Autodesk Fusion 360 part; units mm, degrees
(part 2 of 2)
sketch "Slot 2 50 constrained seed (3)" plane through (0, 0, 0) normal (0, 0, 1) x (1, 0, 0) in component "Solid-land M3"
  line L0 (167.5, 45) -> (167.5, 55)
  arc A0 (167.5, 55) -> (162.5, 55) centre (165, 55) ccw
  line L1 (162.5, 55) -> (162.5, 45)
  arc A1 (162.5, 45) -> (167.5, 45) centre (165, 45) ccw
  line L2 (165, 45) -> (165, 55) construction
  line L3 (165, 45) -> (175, 45) construction
  dimension "d538" = 5
  dimension "d539" = 10
  dimension "d540" = 90
  dimension "d541" = 10
  dimension "d542" = 165
  dimension "d543" = 45
  constraint tangent L0 A0
  constraint tangent A0 L1
  constraint tangent L1 A1
  constraint tangent L0 A1
  constraint parallel L0 L1
  constraint horizontal L3
  measures "d538" diameter of A0
  measures "d539" distance of A1.centre A0.centre
  measures "d540" angle of L2 L3
  measures "d541" horizontal distance of A1.centre L3.end
  measures "d542" horizontal distance of origin A1.centre
  measures "d543" vertical distance of origin A1.centre
extrude "Slot 2 50 through cut''" cut sketch "Slot 2 50 constrained seed (3)" along normal blind 5 bodies 3 in component "Solid-land M3"
pattern_linear "Slot 2 50 lattice''" count 1 spacing 20 along (1, 0, 0) of "Slot 2 50 through cut''" in component "Solid-land M3"
sketch "Slot 3 20 constrained seed (3)" plane through (0, 0, 0) normal (0, 0, 1) x (1, 0, 0) in component "Solid-land M3"
  line L0 (177.5, 15) -> (177.5, 25)
  arc A0 (177.5, 25) -> (172.5, 25) centre (175, 25) ccw
  line L1 (172.5, 25) -> (172.5, 15)
  arc A1 (172.5, 15) -> (177.5, 15) centre (175, 15) ccw
  line L2 (175, 15) -> (175, 25) construction
  line L3 (175, 15) -> (185, 15) construction
  dimension "d550" = 5
  dimension "d551" = 10
  dimension "d552" = 90
  dimension "d553" = 10
  dimension "d554" = 175
  dimension "d555" = 15
  constraint tangent L0 A0
  constraint tangent A0 L1
  constraint tangent L1 A1
  constraint tangent L0 A1
  constraint parallel L0 L1
  constraint horizontal L3
  measures "d550" diameter of A0
  measures "d551" distance of A1.centre A0.centre
  measures "d552" angle of L2 L3
  measures "d553" horizontal distance of A1.centre L3.end
  measures "d554" horizontal distance of origin A1.centre
  measures "d555" vertical distance of origin A1.centre
extrude "Slot 3 20 through cut''" cut sketch "Slot 3 20 constrained seed (3)" along normal blind 5 bodies 3 in component "Solid-land M3"
pattern_linear "Slot 3 20 lattice''" count 1 spacing 20 along (1, 0, 0) of "Slot 3 20 through cut''" in component "Solid-land M3"
sketch "Slot 3 40 constrained seed (3)" plane through (0, 0, 0) normal (0, 0, 1) x (1, 0, 0) in component "Solid-land M3"
  line L0 (177.5, 35) -> (177.5, 45)
  arc A0 (177.5, 45) -> (172.5, 45) centre (175, 45) ccw
  line L1 (172.5, 45) -> (172.5, 35)
  arc A1 (172.5, 35) -> (177.5, 35) centre (175, 35) ccw
  line L2 (175, 35) -> (175, 45) construction
  line L3 (175, 35) -> (185, 35) construction
  dimension "d562" = 5
  dimension "d563" = 10
  dimension "d564" = 90
  dimension "d565" = 10
  dimension "d566" = 175
  dimension "d567" = 35
  constraint tangent L0 A0
  constraint tangent A0 L1
  constraint tangent L1 A1
  constraint tangent L0 A1
  constraint parallel L0 L1
  constraint horizontal L3
  measures "d562" diameter of A0
  measures "d563" distance of A1.centre A0.centre
  measures "d564" angle of L2 L3
  measures "d565" horizontal distance of A1.centre L3.end
  measures "d566" horizontal distance of origin A1.centre
  measures "d567" vertical distance of origin A1.centre
extrude "Slot 3 40 through cut''" cut sketch "Slot 3 40 constrained seed (3)" along normal blind 5 bodies 3 in component "Solid-land M3"
pattern_linear "Slot 3 40 lattice''" count 1 spacing 20 along (1, 0, 0) of "Slot 3 40 through cut''" in component "Solid-land M3"
sketch "Slot 4 10 constrained seed (3)" plane through (0, 0, 0) normal (0, 0, 1) x (1, 0, 0) in component "Solid-land M3"
  line L0 (187.5, 5) -> (187.5, 15)
  arc A0 (187.5, 15) -> (182.5, 15) centre (185, 15) ccw
  line L1 (182.5, 15) -> (182.5, 5)
  arc A1 (182.5, 5) -> (187.5, 5) centre (185, 5) ccw
  line L2 (185, 5) -> (185, 15) construction
  line L3 (185, 5) -> (195, 5) construction
  dimension "d574" = 5
  dimension "d575" = 10
  dimension "d576" = 90
  dimension "d577" = 10
  dimension "d578" = 185
  dimension "d579" = 5
  constraint tangent L0 A0
  constraint tangent A0 L1
  constraint tangent L1 A1
  constraint tangent L0 A1
  constraint parallel L0 L1
  constraint horizontal L3
  measures "d574" diameter of A0
  measures "d575" distance of A1.centre A0.centre
  measures "d576" angle of L2 L3
  measures "d577" horizontal distance of A1.centre L3.end
  measures "d578" horizontal distance of origin A1.centre
  measures "d579" vertical distance of origin A1.centre
extrude "Slot 4 10 through cut''" cut sketch "Slot 4 10 constrained seed (3)" along normal blind 5 bodies 3 in component "Solid-land M3"
pattern_linear "Slot 4 10 lattice''" count 1 spacing 20 along (1, 0, 0) of "Slot 4 10 through cut''" in component "Solid-land M3"
sketch "Slot 4 30 constrained seed (3)" plane through (0, 0, 0) normal (0, 0, 1) x (1, 0, 0) in component "Solid-land M3"
  line L0 (187.5, 25) -> (187.5, 35)
  arc A0 (187.5, 35) -> (182.5, 35) centre (185, 35) ccw
  line L1 (182.5, 35) -> (182.5, 25)
  arc A1 (182.5, 25) -> (187.5, 25) centre (185, 25) ccw
  line L2 (185, 25) -> (185, 35) construction
  line L3 (185, 25) -> (195, 25) construction
  dimension "d586" = 5
  dimension "d587" = 10
  dimension "d588" = 90
  dimension "d589" = 10
  dimension "d590" = 185
  dimension "d591" = 25
  constraint tangent L0 A0
  constraint tangent A0 L1
  constraint tangent L1 A1
  constraint tangent L0 A1
  constraint parallel L0 L1
  constraint horizontal L3
  measures "d586" diameter of A0
  measures "d587" distance of A1.centre A0.centre
  measures "d588" angle of L2 L3
  measures "d589" horizontal distance of A1.centre L3.end
  measures "d590" horizontal distance of origin A1.centre
  measures "d591" vertical distance of origin A1.centre
extrude "Slot 4 30 through cut''" cut sketch "Slot 4 30 constrained seed (3)" along normal blind 5 bodies 3 in component "Solid-land M3"
pattern_linear "Slot 4 30 lattice''" count 1 spacing 20 along (1, 0, 0) of "Slot 4 30 through cut''" in component "Solid-land M3"
sketch "Slot 4 50 constrained seed (3)" plane through (0, 0, 0) normal (0, 0, 1) x (1, 0, 0) in component "Solid-land M3"
  line L0 (187.5, 45) -> (187.5, 55)
  arc A0 (187.5, 55) -> (182.5, 55) centre (185, 55) ccw
  line L1 (182.5, 55) -> (182.5, 45)
  arc A1 (182.5, 45) -> (187.5, 45) centre (185, 45) ccw
  line L2 (185, 45) -> (185, 55) construction
  line L3 (185, 45) -> (195, 45) construction
  dimension "d598" = 5
  dimension "d599" = 10
  dimension "d600" = 90
  dimension "d601" = 10
  dimension "d602" = 185
  dimension "d603" = 45
  constraint tangent L0 A0
  constraint tangent A0 L1
  constraint tangent L1 A1
  constraint tangent L0 A1
  constraint parallel L0 L1
  constraint horizontal L3
  measures "d598" diameter of A0
  measures "d599" distance of A1.centre A0.centre
  measures "d600" angle of L2 L3
  measures "d601" horizontal distance of A1.centre L3.end
  measures "d602" horizontal distance of origin A1.centre
  measures "d603" vertical distance of origin A1.centre
extrude "Slot 4 50 through cut''" cut sketch "Slot 4 50 constrained seed (3)" along normal blind 5 bodies 3 in component "Solid-land M3"
pattern_linear "Slot 4 50 lattice''" count 1 spacing 20 along (1, 0, 0) of "Slot 4 50 through cut''" in component "Solid-land M3"
sketch "Slot 5 20 constrained seed (3)" plane through (0, 0, 0) normal (0, 0, 1) x (1, 0, 0) in component "Solid-land M3"
  line L0 (197.5, 15) -> (197.5, 25)
  arc A0 (197.5, 25) -> (192.5, 25) centre (195, 25) ccw
  line L1 (192.5, 25) -> (192.5, 15)
  arc A1 (192.5, 15) -> (197.5, 15) centre (195, 15) ccw
  line L2 (195, 15) -> (195, 25) construction
  line L3 (195, 15) -> (205, 15) construction
  dimension "d610" = 5
  dimension "d611" = 10
  dimension "d612" = 90
  dimension "d613" = 10
  dimension "d614" = 195
  dimension "d615" = 15
  constraint tangent L0 A0
  constraint tangent A0 L1
  constraint tangent L1 A1
  constraint tangent L0 A1
  constraint parallel L0 L1
  constraint horizontal L3
  measures "d610" diameter of A0
  measures "d611" distance of A1.centre A0.centre
  measures "d612" angle of L2 L3
  measures "d613" horizontal distance of A1.centre L3.end
  measures "d614" horizontal distance of origin A1.centre
  measures "d615" vertical distance of origin A1.centre
extrude "Slot 5 20 through cut''" cut sketch "Slot 5 20 constrained seed (3)" along normal blind 5 bodies 3 in component "Solid-land M3"
pattern_linear "Slot 5 20 lattice''" count 1 spacing 20 along (1, 0, 0) of "Slot 5 20 through cut''" in component "Solid-land M3"
sketch "Slot 5 40 constrained seed (3)" plane through (0, 0, 0) normal (0, 0, 1) x (1, 0, 0) in component "Solid-land M3"
  line L0 (197.5, 35) -> (197.5, 45)
  arc A0 (197.5, 45) -> (192.5, 45) centre (195, 45) ccw
  line L1 (192.5, 45) -> (192.5, 35)
  arc A1 (192.5, 35) -> (197.5, 35) centre (195, 35) ccw
  line L2 (195, 35) -> (195, 45) construction
  line L3 (195, 35) -> (205, 35) construction
  dimension "d622" = 5
  dimension "d623" = 10
  dimension "d624" = 90
  dimension "d625" = 10
  dimension "d626" = 195
  dimension "d627" = 35
  constraint tangent L0 A0
  constraint tangent A0 L1
  constraint tangent L1 A1
  constraint tangent L0 A1
  constraint parallel L0 L1
  constraint horizontal L3
  measures "d622" diameter of A0
  measures "d623" distance of A1.centre A0.centre
  measures "d624" angle of L2 L3
  measures "d625" horizontal distance of A1.centre L3.end
  measures "d626" horizontal distance of origin A1.centre
  measures "d627" vertical distance of origin A1.centre
extrude "Slot 5 40 through cut''" cut sketch "Slot 5 40 constrained seed (3)" along normal blind 5 bodies 3 in component "Solid-land M3"
pattern_linear "Slot 5 40 lattice''" count 1 spacing 20 along (1, 0, 0) of "Slot 5 40 through cut''" in component "Solid-land M3"
fillet "Rounded entrances''" radius 0.4 2 faces at (194.1044, 5.8357, 0) (194.1044, 5.8357, 0) on bodies 3 in component "Solid-land M3"
sketch "Mount bore sketch (3)" plane through (0, 0, 0) normal (0, 0, 1) x (1, 0, 0) in component "Solid-land M3"
  circle A0 centre (165, 30) radius 1.7
  dimension "d636" = 165
  dimension "d637" = 30
  dimension "d638" = 3.4
  measures "d636" horizontal distance of origin A0.centre
  measures "d637" vertical distance of origin A0.centre
  measures "d638" diameter of A0
extrude "Mount bore''" cut sketch "Mount bore sketch (3)" along normal blind 5 bodies 3 in component "Solid-land M3"
sketch "Flush screw seat sketch (3)" plane through (0, 0, 0) normal (0, 0, 1) x (1, 0, 0) in component "Solid-land M3"
  circle A0 centre (165, 30) radius 3.1
  dimension "d641" = 165
  dimension "d642" = 30
  dimension "d643" = 6.2
  measures "d641" horizontal distance of origin A0.centre
  measures "d642" vertical distance of origin A0.centre
  measures "d643" diameter of A0
extrude "Flush screw seat''" cut sketch "Flush screw seat sketch (3)" along normal blind 1.4 draft -45 bodies 3 in component "Solid-land M3"
component "Original M2" placed x (1, 0, 0) y (0, 1, 0) z (0, 0, 1) at (0, 0, 0)
component "Centered M2" placed x (1, 0, 0) y (0, 1, 0) z (0, 0, 1) at (0, 0, 0)
component "Solid-land M3" placed x (1, 0, 0) y (0, 1, 0) z (0, 0, 1) at (0, 0, 0)
equation "columns = 12" comment "Even integer 4..14; each cell is 20 mm"
equation "rows = 12" comment "Even integer 4..14"
equation "pitch = 20 mm" comment "Keep for dense SKADIS compatible lattice"
equation "panelWidth = columns * pitch" comment "Nominal module pitch X"
equation "panelHeight = rows * pitch" comment "Nominal module pitch Y"
equation "seamGap = 0.35 mm" comment "Physical envelope shrinks around fixed lattice"
equation "boardThickness = 5 mm" comment "Fit-test with real hooks"
equation "slotWidth = 5 mm" comment "Minimum throat width"
equation "slotHeight = 15 mm" comment "Minimum throat height"
equation "entryRadius = 0.4 mm" comment "Front slot and perimeter edge rounding"
equation "cornerRadius = 6 mm" comment "Plan-view panel corner rounding"
equation "hookClearance = 10 mm" comment "PROVISIONAL unobstructed depth behind board; carriers begin at its rear boundary"
equation "frameZ = carrierZ + carrierThickness" comment "Front extrusion datum"
equation "profileMouth = 6.28 mm" comment "User measured mouth"
equation "profileCavity = 11 mm" comment "User measured widest cavity"
equation "profileDepth = 6.2 mm" comment "User measured face-to-floor depth"
equation "profileFloor = 5.7 mm" comment "User estimate, lower confidence"
equation "profileLip = 1.5 mm" comment "Unmeasured; tentative comparable catalog value"
equation "profileTaperStart = profileDepth - ( profileCavity - profileFloor ) / 2" comment "Assumed 45-degree inner slopes"
equation "profileBore = 5 mm" comment "Unmeasured central bore, reference only"
equation "nutWidth = 8.8 mm" comment "Provisional low-profile METAL T-nut envelope, not old rectangular carrier"
equation "nutLength = 12 mm" comment "End-loaded anti-rotation metal nut envelope"
equation "nutThickness = 2.7 mm" comment "Thin nut reference; fit/load still unverified"
equation "jointLeg = 18 mm" comment "In-bay angle footprint"
equation "jointThickness = 3 mm" comment "Metal bracket thickness"
equation "jointDepth = 16 mm" comment "Bracket depth within 20 mm rail"
equation "sideScrewLength = 8 mm" comment "M5x8 reference; check against actual bracket and nut"
equation "wallTabHeight = 24 mm" comment "Tab along extrusion"
equation "wallTabReach = 22 mm" comment "Tab into open bay"
equation "wallAnchorClearance = 6.5 mm" comment "Placeholder wall anchor interface"
equation "wallDriverDiameter = 12 mm" comment "Clear tool envelope in open bays"
equation "keyDriverDiameter = 5 mm" comment "Short hex-key working-leg envelope"
equation "keyDriverReach = 20 mm" comment "Short hex-key working-leg reach"
equation "supportWidth = 3.2 mm" comment "Prototype blade; two perimeter lines need print review"
equation "supportLength = 12 mm" comment "Compression bearing length"
equation "hookEnvelopeWidth = 6 mm" comment "Conservative provisional continuous hook column"
equation "carrierThickness = 7 mm" comment "Room for captive M2 nut and stock M5x12"
equation "panelClearance = 2.4 mm" comment "M2 clearance"
equation "panelHeadPocket = 4 mm" comment "DIN965 3.8 mm head plus 0.1 mm recess"
equation "carrierHeadPocket = 9.4 mm" comment "DIN965 M5 9.2 mm head plus recess"
equation "carrierBore = 5.5 mm" comment "M5 clearance"
equation "tongueWidth = 2.8 mm" comment "Rear axial registration tongue"
equation "tongueLength = 8 mm" comment "Axial release registration"
equation "tongueDepth = 0.6 mm" comment "Tongue engagement"
equation "registerClearance = 0.2 mm" comment "Each side of printed tongue"
equation "carrierZ = boardThickness + hookClearance" comment "Rear hook cavity boundary"
equation "stepCorner = 0.6 mm" comment "Small plan corner relief; printed fit remains untested"
equation "webCenterOffset = ( pitch / 2 - ( pitch - ( slotHeight - slotWidth ) ) / 2 ) ^ 2 / pitch" comment "Equal clearance to three adjacent slot outlines; 1.25 mm at standard lattice"
equation "d70 = boardThickness"
equation "d72 = slotWidth"
equation "d73 = slotHeight - slotWidth"
equation "d75 = pitch / 2"
equation "d76 = abs(5 mm)"
equation "d77 = abs(( 10 mm ) - ( slotHeight - slotWidth ) / 2)"
equation "d78 = boardThickness"
equation "d82 = pitch"
equation "d83 = pitch"
equation "d84 = slotWidth"
equation "d85 = slotHeight - slotWidth"
equation "d87 = pitch / 2"
equation "d88 = abs(5 mm)"
equation "d89 = abs(( 30 mm ) - ( slotHeight - slotWidth ) / 2)"
equation "d90 = boardThickness"
equation "d94 = pitch"
equation "d95 = pitch"
equation "d96 = slotWidth"
equation "d97 = slotHeight - slotWidth"
equation "d99 = pitch / 2"
equation "d100 = abs(5 mm)"
equation "d101 = abs(( 50 mm ) - ( slotHeight - slotWidth ) / 2)"
equation "d102 = boardThickness"
equation "d106 = pitch"
equation "d107 = pitch"
equation "d108 = slotWidth"
equation "d109 = slotHeight - slotWidth"
equation "d111 = pitch / 2"
equation "d112 = abs(15 mm)"
equation "d113 = abs(( 20 mm ) - ( slotHeight - slotWidth ) / 2)"
equation "d114 = boardThickness"
equation "d118 = pitch"
equation "d119 = pitch"
equation "d120 = slotWidth"
equation "d121 = slotHeight - slotWidth"
equation "d123 = pitch / 2"
equation "d124 = abs(15 mm)"
equation "d125 = abs(( 40 mm ) - ( slotHeight - slotWidth ) / 2)"
equation "d126 = boardThickness"
equation "d130 = pitch"
equation "d131 = pitch"
equation "d132 = slotWidth"
equation "d133 = slotHeight - slotWidth"
equation "d135 = pitch / 2"
equation "d136 = abs(25 mm)"
equation "d137 = abs(( 10 mm ) - ( slotHeight - slotWidth ) / 2)"
equation "d138 = boardThickness"
equation "d142 = pitch"
equation "d143 = pitch"
equation "d144 = slotWidth"
equation "d145 = slotHeight - slotWidth"
equation "d147 = pitch / 2"
equation "d148 = abs(25 mm)"
equation "d149 = abs(( 30 mm ) - ( slotHeight - slotWidth ) / 2)"
equation "d150 = boardThickness"
equation "d154 = pitch"
equation "d155 = pitch"
equation "d156 = slotWidth"
equation "d157 = slotHeight - slotWidth"
equation "d159 = pitch / 2"
equation "d160 = abs(25 mm)"
equation "d161 = abs(( 50 mm ) - ( slotHeight - slotWidth ) / 2)"
equation "d162 = boardThickness"
equation "d166 = pitch"
equation "d167 = pitch"
equation "d168 = slotWidth"
equation "d169 = slotHeight - slotWidth"
equation "d171 = pitch / 2"
equation "d172 = abs(35 mm)"
equation "d173 = abs(( 20 mm ) - ( slotHeight - slotWidth ) / 2)"
equation "d174 = boardThickness"
equation "d178 = pitch"
equation "d179 = pitch"
equation "d180 = slotWidth"
equation "d181 = slotHeight - slotWidth"
equation "d183 = pitch / 2"
equation "d184 = abs(35 mm)"
equation "d185 = abs(( 40 mm ) - ( slotHeight - slotWidth ) / 2)"
equation "d186 = boardThickness"
equation "d190 = pitch"
equation "d191 = pitch"
equation "d192 = slotWidth"
equation "d193 = slotHeight - slotWidth"
equation "d195 = pitch / 2"
equation "d196 = abs(45 mm)"
equation "d197 = abs(( 10 mm ) - ( slotHeight - slotWidth ) / 2)"
equation "d198 = boardThickness"
equation "d202 = pitch"
equation "d203 = pitch"
equation "d204 = slotWidth"
equation "d205 = slotHeight - slotWidth"
equation "d207 = pitch / 2"
equation "d208 = abs(45 mm)"
equation "d209 = abs(( 30 mm ) - ( slotHeight - slotWidth ) / 2)"
equation "d210 = boardThickness"
equation "d214 = pitch"
equation "d215 = pitch"
equation "d216 = slotWidth"
equation "d217 = slotHeight - slotWidth"
equation "d219 = pitch / 2"
equation "d220 = abs(45 mm)"
equation "d221 = abs(( 50 mm ) - ( slotHeight - slotWidth ) / 2)"
equation "d222 = boardThickness"
equation "d226 = pitch"
equation "d227 = pitch"
equation "d228 = slotWidth"
equation "d229 = slotHeight - slotWidth"
equation "d231 = pitch / 2"
equation "d232 = abs(55 mm)"
equation "d233 = abs(( 20 mm ) - ( slotHeight - slotWidth ) / 2)"
equation "d234 = boardThickness"
equation "d238 = pitch"
equation "d239 = pitch"
equation "d240 = slotWidth"
equation "d241 = slotHeight - slotWidth"
equation "d243 = pitch / 2"
equation "d244 = abs(55 mm)"
equation "d245 = abs(( 40 mm ) - ( slotHeight - slotWidth ) / 2)"
equation "d246 = boardThickness"
equation "d250 = pitch"
equation "d251 = pitch"
equation "d253 = entryRadius"
equation "d254 = abs(30 mm)"
equation "d255 = abs(20 mm)"
equation "d257 = boardThickness"
equation "d259 = abs(30 mm)"
equation "d260 = abs(20 mm)"
equation "d262 = ( 4 mm - 2.4 mm ) / 2"
equation "d264 = abs(70 mm)"
equation "d267 = boardThickness"
equation "d269 = slotWidth"
equation "d270 = slotHeight - slotWidth"
equation "d272 = pitch / 2"
equation "d273 = abs(75 mm)"
equation "d274 = abs(( 10 mm ) - ( slotHeight - slotWidth ) / 2)"
equation "d275 = boardThickness"
equation "d279 = pitch"
equation "d280 = pitch"
equation "d281 = slotWidth"
equation "d282 = slotHeight - slotWidth"
equation "d284 = pitch / 2"
equation "d285 = abs(75 mm)"
equation "d286 = abs(( 30 mm ) - ( slotHeight - slotWidth ) / 2)"
equation "d287 = boardThickness"
equation "d291 = pitch"
equation "d292 = pitch"
equation "d293 = slotWidth"
equation "d294 = slotHeight - slotWidth"
equation "d296 = pitch / 2"
equation "d297 = abs(75 mm)"
equation "d298 = abs(( 50 mm ) - ( slotHeight - slotWidth ) / 2)"
equation "d299 = boardThickness"
equation "d303 = pitch"
equation "d304 = pitch"
equation "d305 = slotWidth"
equation "d306 = slotHeight - slotWidth"
equation "d308 = pitch / 2"
equation "d309 = abs(85 mm)"
equation "d310 = abs(( 20 mm ) - ( slotHeight - slotWidth ) / 2)"
equation "d311 = boardThickness"
equation "d315 = pitch"
equation "d316 = pitch"
equation "d317 = slotWidth"
equation "d318 = slotHeight - slotWidth"
equation "d320 = pitch / 2"
equation "d321 = abs(85 mm)"
equation "d322 = abs(( 40 mm ) - ( slotHeight - slotWidth ) / 2)"
equation "d323 = boardThickness"
equation "d327 = pitch"
equation "d328 = pitch"
equation "d329 = slotWidth"
equation "d330 = slotHeight - slotWidth"
equation "d332 = pitch / 2"
equation "d333 = abs(95 mm)"
equation "d334 = abs(( 10 mm ) - ( slotHeight - slotWidth ) / 2)"
equation "d335 = boardThickness"
equation "d339 = pitch"
equation "d340 = pitch"
equation "d341 = slotWidth"
equation "d342 = slotHeight - slotWidth"
equation "d344 = pitch / 2"
equation "d345 = abs(95 mm)"
equation "d346 = abs(( 30 mm ) - ( slotHeight - slotWidth ) / 2)"
equation "d347 = boardThickness"
equation "d351 = pitch"
equation "d352 = pitch"
equation "d353 = slotWidth"
equation "d354 = slotHeight - slotWidth"
equation "d356 = pitch / 2"
equation "d357 = abs(95 mm)"
equation "d358 = abs(( 50 mm ) - ( slotHeight - slotWidth ) / 2)"
equation "d359 = boardThickness"
equation "d363 = pitch"
equation "d364 = pitch"
equation "d365 = slotWidth"
equation "d366 = slotHeight - slotWidth"
equation "d368 = pitch / 2"
equation "d369 = abs(105 mm)"
equation "d370 = abs(( 20 mm ) - ( slotHeight - slotWidth ) / 2)"
equation "d371 = boardThickness"
equation "d375 = pitch"
equation "d376 = pitch"
equation "d377 = slotWidth"
equation "d378 = slotHeight - slotWidth"
equation "d380 = pitch / 2"
equation "d381 = abs(105 mm)"
equation "d382 = abs(( 40 mm ) - ( slotHeight - slotWidth ) / 2)"
equation "d383 = boardThickness"
equation "d387 = pitch"
equation "d388 = pitch"
equation "d389 = slotWidth"
equation "d390 = slotHeight - slotWidth"
equation "d392 = pitch / 2"
equation "d393 = abs(115 mm)"
equation "d394 = abs(( 10 mm ) - ( slotHeight - slotWidth ) / 2)"
equation "d395 = boardThickness"
equation "d399 = pitch"
equation "d400 = pitch"
equation "d401 = slotWidth"
equation "d402 = slotHeight - slotWidth"
equation "d404 = pitch / 2"
equation "d405 = abs(115 mm)"
equation "d406 = abs(( 30 mm ) - ( slotHeight - slotWidth ) / 2)"
equation "d407 = boardThickness"
equation "d411 = pitch"
equation "d412 = pitch"
equation "d413 = slotWidth"
equation "d414 = slotHeight - slotWidth"
equation "d416 = pitch / 2"
equation "d417 = abs(115 mm)"
equation "d418 = abs(( 50 mm ) - ( slotHeight - slotWidth ) / 2)"
equation "d419 = boardThickness"
equation "d423 = pitch"
equation "d424 = pitch"
equation "d425 = slotWidth"
equation "d426 = slotHeight - slotWidth"
equation "d428 = pitch / 2"
equation "d429 = abs(125 mm)"
equation "d430 = abs(( 20 mm ) - ( slotHeight - slotWidth ) / 2)"
equation "d431 = boardThickness"
equation "d435 = pitch"
equation "d436 = pitch"
equation "d437 = slotWidth"
equation "d438 = slotHeight - slotWidth"
equation "d440 = pitch / 2"
equation "d441 = abs(125 mm)"
equation "d442 = abs(( 40 mm ) - ( slotHeight - slotWidth ) / 2)"
equation "d443 = boardThickness"
equation "d447 = pitch"
equation "d448 = pitch"
equation "d450 = entryRadius"
equation "d451 = abs(100 mm - webCenterOffset)"
equation "d452 = abs(20 mm)"
equation "d454 = boardThickness"
equation "d456 = abs(100 mm - webCenterOffset)"
equation "d457 = abs(20 mm)"
equation "d459 = ( 4 mm - 2.4 mm ) / 2"
equation "d461 = abs(140 mm)"
equation "d464 = boardThickness"
equation "d466 = slotWidth"
equation "d467 = slotHeight - slotWidth"
equation "d469 = pitch / 2"
equation "d470 = abs(145 mm)"
equation "d471 = abs(( 10 mm ) - ( slotHeight - slotWidth ) / 2)"
equation "d472 = boardThickness"
equation "d476 = pitch"
equation "d477 = pitch"
equation "d478 = slotWidth"
equation "d479 = slotHeight - slotWidth"
equation "d481 = pitch / 2"
equation "d482 = abs(145 mm)"
equation "d483 = abs(( 30 mm ) - ( slotHeight - slotWidth ) / 2)"
equation "d484 = boardThickness"
equation "d488 = pitch"
equation "d489 = pitch"
equation "d490 = slotWidth"
equation "d491 = slotHeight - slotWidth"
equation "d493 = pitch / 2"
equation "d494 = abs(145 mm)"
equation "d495 = abs(( 50 mm ) - ( slotHeight - slotWidth ) / 2)"
equation "d496 = boardThickness"
equation "d500 = pitch"
equation "d501 = pitch"
equation "d502 = slotWidth"
equation "d503 = slotHeight - slotWidth"
equation "d505 = pitch / 2"
equation "d506 = abs(155 mm)"
equation "d507 = abs(( 20 mm ) - ( slotHeight - slotWidth ) / 2)"
equation "d508 = boardThickness"
equation "d512 = pitch"
equation "d513 = pitch"
equation "d514 = slotWidth"
equation "d515 = slotHeight - slotWidth"
equation "d517 = pitch / 2"
equation "d518 = abs(155 mm)"
equation "d519 = abs(( 40 mm ) - ( slotHeight - slotWidth ) / 2)"
equation "d520 = boardThickness"
equation "d524 = pitch"
equation "d525 = pitch"
equation "d526 = slotWidth"
equation "d527 = slotHeight - slotWidth"
equation "d529 = pitch / 2"
equation "d530 = abs(165 mm)"
equation "d531 = abs(( 10 mm ) - ( slotHeight - slotWidth ) / 2)"
equation "d532 = boardThickness"
equation "d536 = pitch"
equation "d537 = pitch"
equation "d538 = slotWidth"
equation "d539 = slotHeight - slotWidth"
equation "d541 = pitch / 2"
equation "d542 = abs(165 mm)"
equation "d543 = abs(( 50 mm ) - ( slotHeight - slotWidth ) / 2)"
equation "d544 = boardThickness"
equation "d548 = pitch"
equation "d549 = pitch"
equation "d550 = slotWidth"
equation "d551 = slotHeight - slotWidth"
equation "d553 = pitch / 2"
equation "d554 = abs(175 mm)"
equation "d555 = abs(( 20 mm ) - ( slotHeight - slotWidth ) / 2)"
equation "d556 = boardThickness"
equation "d560 = pitch"
equation "d561 = pitch"
equation "d562 = slotWidth"
equation "d563 = slotHeight - slotWidth"
equation "d565 = pitch / 2"
equation "d566 = abs(175 mm)"
equation "d567 = abs(( 40 mm ) - ( slotHeight - slotWidth ) / 2)"
equation "d568 = boardThickness"
equation "d572 = pitch"
equation "d573 = pitch"
equation "d574 = slotWidth"
equation "d575 = slotHeight - slotWidth"
equation "d577 = pitch / 2"
equation "d578 = abs(185 mm)"
equation "d579 = abs(( 10 mm ) - ( slotHeight - slotWidth ) / 2)"
equation "d580 = boardThickness"
equation "d584 = pitch"
equation "d585 = pitch"
equation "d586 = slotWidth"
equation "d587 = slotHeight - slotWidth"
equation "d589 = pitch / 2"
equation "d590 = abs(185 mm)"
equation "d591 = abs(( 30 mm ) - ( slotHeight - slotWidth ) / 2)"
equation "d592 = boardThickness"
equation "d596 = pitch"
equation "d597 = pitch"
equation "d598 = slotWidth"
equation "d599 = slotHeight - slotWidth"
equation "d601 = pitch / 2"
equation "d602 = abs(185 mm)"
equation "d603 = abs(( 50 mm ) - ( slotHeight - slotWidth ) / 2)"
equation "d604 = boardThickness"
equation "d608 = pitch"
equation "d609 = pitch"
equation "d610 = slotWidth"
equation "d611 = slotHeight - slotWidth"
equation "d613 = pitch / 2"
equation "d614 = abs(195 mm)"
equation "d615 = abs(( 20 mm ) - ( slotHeight - slotWidth ) / 2)"
equation "d616 = boardThickness"
equation "d620 = pitch"
equation "d621 = pitch"
equation "d622 = slotWidth"
equation "d623 = slotHeight - slotWidth"
equation "d625 = pitch / 2"
equation "d626 = abs(195 mm)"
equation "d627 = abs(( 40 mm ) - ( slotHeight - slotWidth ) / 2)"
equation "d628 = boardThickness"
equation "d632 = pitch"
equation "d633 = pitch"
equation "d635 = entryRadius"
equation "d636 = abs(165 mm)"
equation "d637 = abs(30 mm)"
equation "d639 = boardThickness"
equation "d641 = abs(165 mm)"
equation "d642 = abs(30 mm)"
equation "d644 = ( 6.2 mm - 3.4 mm ) / 2"
